Autodesk Fusion 360 part; units mm, degrees
(part 2 of 3)
extrude "Ламель 100 мм с пазами''''''''''''''''''" add sketch "Sketch1 (28)" along normal blind 16 separate body makes body 28 in component "Ламель ДСП 16 — 19"
ref_plane "WorkPlane2" through (0, 0, 0) normal (0, 1, 0) x (0, 0, 1) in component "Ламель ДСП 16 — 19"
sketch "Sketch2 (10)" plane through (0, 0, 0) normal (0, 1, 0) x (1, 0, 0) in component "Ламель ДСП 16 — 19"
  line L0 (-10, 8) -> (0.2209, 8)
  arc A0 (0.2209, 8) -> (0.2209, -8) centre (145, 0) ccw
  line L1 (0.2209, -8) -> (-10, -8)
  line L2 (-10, -8) -> (-10, 8)
extrude "Подгонка по радиусу наружной облицовки (4)" [suppressed] in component "ХДФ 3 — наружная обшивка — 2 шт"
extrude "Extrude11" [no effect] in component "Полистирол 2 — наружная обшивка — 2 шт"
extrude "Extrude2'''''''" cut sketch "Sketch2 (10)" along normal blind 998 bodies 28 in component "Ламель ДСП 16 — 19"
ref_plane "WorkPlane1" through (0, 0, -8) normal (0, 0, 1) x (1, 0, 0) in component "Ламель ДСП 16 — 20"
sketch "Sketch1 (29)" plane through (0, 0, -8) normal (0, 0, 1) x (1, 0, 0) in component "Ламель ДСП 16 — 20"
  line L0 (0, 0) -> (50, 0)
  line L1 (50, 0) -> (50, 16)
  line L2 (50, 16) -> (100, 16)
  line L3 (100, 16) -> (100, 245.5)
  line L4 (100, 245.5) -> (50, 245.5)
  line L5 (50, 245.5) -> (50, 261.5)
  line L6 (50, 261.5) -> (100, 261.5)
  line L7 (100, 261.5) -> (100, 491)
  line L8 (100, 491) -> (50, 491)
  line L9 (50, 491) -> (50, 507)
  line L10 (50, 507) -> (100, 507)
  line L11 (100, 507) -> (100, 736.5)
  line L12 (100, 736.5) -> (50, 736.5)
  line L13 (50, 736.5) -> (50, 752.5)
  line L14 (50, 752.5) -> (100, 752.5)
  line L15 (100, 752.5) -> (100, 982)
  line L16 (100, 982) -> (12.5, 982)
  line L17 (12.5, 982) -> (12.5, 998)
  line L18 (12.5, 998) -> (0, 998)
  line L19 (0, 998) -> (0, 0)
extrude "Ламель 100 мм с пазами'''''''''''''''''''" add sketch "Sketch1 (29)" along normal blind 16 separate body makes body 29 in component "Ламель ДСП 16 — 20"
ref_plane "WorkPlane2" through (0, 0, 0) normal (0, 1, 0) x (0, 0, 1) in component "Ламель ДСП 16 — 20"
sketch "Sketch2 (11)" plane through (0, 0, 0) normal (0, 1, 0) x (1, 0, 0) in component "Ламель ДСП 16 — 20"
  line L0 (-10, 8) -> (0.2209, 8)
  arc A0 (0.2209, 8) -> (0.2209, -8) centre (145, 0) ccw
  line L1 (0.2209, -8) -> (-10, -8)
  line L2 (-10, -8) -> (-10, 8)
extrude "Подгонка по радиусу наружной облицовки (5)" [suppressed] in component "ХДФ 3 — наружная обшивка — 2 шт"
extrude "Extrude12" [no effect] in component "Полистирол 2 — наружная обшивка — 2 шт"
extrude "Extrude2''''''''" cut sketch "Sketch2 (11)" along normal blind 998 bodies 29 in component "Ламель ДСП 16 — 20"
ref_plane "WorkPlane3" through (0, 0, -8) normal (0, 0, 1) x (1, 0, 0) in component "Ламель ДСП 16 — 18"
sketch "Sketch3" plane through (0, 0, -8) normal (0, 0, 1) x (1, 0, 0) in component "Ламель ДСП 16 — 18"
  line L0 (25, 850) -> (101, 850)
  line L1 (101, 850) -> (101, 982)
  line L2 (101, 982) -> (25, 982)
  line L3 (25, 982) -> (25, 850)
extrude "Освободить нишу под цветы" cut sketch "Sketch3" along normal blind 16 bodies 27 in component "Ламель ДСП 16 — 18"
ref_plane "WorkPlane3" through (0, 0, -8) normal (0, 0, 1) x (1, 0, 0) in component "Ламель ДСП 16 — 20"
sketch "Sketch3 (2)" plane through (0, 0, -8) normal (0, 0, 1) x (1, 0, 0) in component "Ламель ДСП 16 — 20"
  line L0 (25, 850) -> (101, 850)
  line L1 (101, 850) -> (101, 982)
  line L2 (101, 982) -> (25, 982)
  line L3 (25, 982) -> (25, 850)
extrude "Освободить нишу под цветы'" cut sketch "Sketch3 (2)" along normal blind 16 bodies 29 in component "Ламель ДСП 16 — 20"
ref_plane "WorkPlane2" through (0, 0, -8) normal (0, 0, 1) x (1, 0, 0) in component "Ламель ДСП 16 — 06"
sketch "Sketch2 (12)" plane through (0, 0, -8) normal (0, 0, 1) x (1, 0, 0) in component "Ламель ДСП 16 — 06"
  line L0 (25, 850) -> (101, 850)
  line L1 (101, 850) -> (101, 982)
  line L2 (101, 982) -> (25, 982)
  line L3 (25, 982) -> (25, 850)
extrude "Освободить нишу под цветы''" cut sketch "Sketch2 (12)" along normal blind 16 bodies 15 in component "Ламель ДСП 16 — 06"
ref_plane "WorkPlane2" through (0, 0, -8) normal (0, 0, 1) x (1, 0, 0) in component "Ламель ДСП 16 — 03"
sketch "Sketch2 (13)" plane through (0, 0, -8) normal (0, 0, 1) x (1, 0, 0) in component "Ламель ДСП 16 — 03"
  line L0 (25, 850) -> (101, 850)
  line L1 (101, 850) -> (101, 982)
  line L2 (101, 982) -> (25, 982)
  line L3 (25, 982) -> (25, 850)
extrude "Освободить нишу под цветы'''" cut sketch "Sketch2 (13)" along normal blind 16 bodies 12 in component "Ламель ДСП 16 — 03"
ref_plane "WorkPlane2" through (0, 0, -8) normal (0, 0, 1) x (1, 0, 0) in component "Ламель ДСП 16 — 04"
sketch "Sketch2 (14)" plane through (0, 0, -8) normal (0, 0, 1) x (1, 0, 0) in component "Ламель ДСП 16 — 04"
  line L0 (25, 850) -> (101, 850)
  line L1 (101, 850) -> (101, 982)
  line L2 (101, 982) -> (25, 982)
  line L3 (25, 982) -> (25, 850)
extrude "Освободить нишу под цветы''''" cut sketch "Sketch2 (14)" along normal blind 16 bodies 13 in component "Ламель ДСП 16 — 04"
ref_plane "WorkPlane2" through (0, 0, -8) normal (0, 0, 1) x (1, 0, 0) in component "Ламель ДСП 16 — 05"
sketch "Sketch2 (15)" plane through (0, 0, -8) normal (0, 0, 1) x (1, 0, 0) in component "Ламель ДСП 16 — 05"
  line L0 (25, 850) -> (101, 850)
  line L1 (101, 850) -> (101, 982)
  line L2 (101, 982) -> (25, 982)
  line L3 (25, 982) -> (25, 850)
extrude "Освободить нишу под цветы'''''" cut sketch "Sketch2 (15)" along normal blind 16 bodies 14 in component "Ламель ДСП 16 — 05"
ref_plane "WorkPlane2" through (0, 0, -8) normal (0, 0, 1) x (1, 0, 0) in component "Ламель ДСП 16 — 07"
sketch "Sketch2 (16)" plane through (0, 0, -8) normal (0, 0, 1) x (1, 0, 0) in component "Ламель ДСП 16 — 07"
  line L0 (25, 850) -> (101, 850)
  line L1 (101, 850) -> (101, 982)
  line L2 (101, 982) -> (25, 982)
  line L3 (25, 982) -> (25, 850)
extrude "Освободить нишу под цветы''''''" cut sketch "Sketch2 (16)" along normal blind 16 bodies 16 in component "Ламель ДСП 16 — 07"
ref_plane "WorkPlane2" through (0, 0, -8) normal (0, 0, 1) x (1, 0, 0) in component "Ламель ДСП 16 — 09"
sketch "Sketch2 (17)" plane through (0, 0, -8) normal (0, 0, 1) x (1, 0, 0) in component "Ламель ДСП 16 — 09"
  line L0 (25, 850) -> (101, 850)
  line L1 (101, 850) -> (101, 982)
  line L2 (101, 982) -> (25, 982)
  line L3 (25, 982) -> (25, 850)
extrude "Освободить нишу под цветы'''''''" cut sketch "Sketch2 (17)" along normal blind 16 bodies 18 in component "Ламель ДСП 16 — 09"
ref_plane "WorkPlane2" through (0, 0, -8) normal (0, 0, 1) x (1, 0, 0) in component "Ламель ДСП 16 — 12"
sketch "Sketch2 (18)" plane through (0, 0, -8) normal (0, 0, 1) x (1, 0, 0) in component "Ламель ДСП 16 — 12"
  line L0 (25, 850) -> (101, 850)
  line L1 (101, 850) -> (101, 982)
  line L2 (101, 982) -> (25, 982)
  line L3 (25, 982) -> (25, 850)
extrude "Освободить нишу под цветы''''''''" cut sketch "Sketch2 (18)" along normal blind 16 bodies 21 in component "Ламель ДСП 16 — 12"
ref_plane "WorkPlane2" through (0, 0, -8) normal (0, 0, 1) x (1, 0, 0) in component "Ламель ДСП 16 — 08"
sketch "Sketch2 (19)" plane through (0, 0, -8) normal (0, 0, 1) x (1, 0, 0) in component "Ламель ДСП 16 — 08"
  line L0 (25, 850) -> (101, 850)
  line L1 (101, 850) -> (101, 982)
  line L2 (101, 982) -> (25, 982)
  line L3 (25, 982) -> (25, 850)
extrude "Освободить нишу под цветы'''''''''" cut sketch "Sketch2 (19)" along normal blind 16 bodies 17 in component "Ламель ДСП 16 — 08"
ref_plane "WorkPlane2" through (0, 0, -8) normal (0, 0, 1) x (1, 0, 0) in component "Ламель ДСП 16 — 10"
sketch "Sketch2 (20)" plane through (0, 0, -8) normal (0, 0, 1) x (1, 0, 0) in component "Ламель ДСП 16 — 10"
  line L0 (25, 850) -> (101, 850)
  line L1 (101, 850) -> (101, 982)
  line L2 (101, 982) -> (25, 982)
  line L3 (25, 982) -> (25, 850)
extrude "Освободить нишу под цветы''''''''''" cut sketch "Sketch2 (20)" along normal blind 16 bodies 19 in component "Ламель ДСП 16 — 10"
ref_plane "WorkPlane2" through (0, 0, -8) normal (0, 0, 1) x (1, 0, 0) in component "Ламель ДСП 16 — 11"
sketch "Sketch2 (21)" plane through (0, 0, -8) normal (0, 0, 1) x (1, 0, 0) in component "Ламель ДСП 16 — 11"
  line L0 (25, 850) -> (101, 850)
  line L1 (101, 850) -> (101, 982)
  line L2 (101, 982) -> (25, 982)
  line L3 (25, 982) -> (25, 850)
extrude "Освободить нишу под цветы'''''''''''" cut sketch "Sketch2 (21)" along normal blind 16 bodies 20 in component "Ламель ДСП 16 — 11"
ref_plane "WorkPlane3" through (0, 0, -8) normal (0, 0, 1) x (1, 0, 0) in component "Ламель ДСП 16 — 16"
sketch "Sketch3 (3)" plane through (0, 0, -8) normal (0, 0, 1) x (1, 0, 0) in component "Ламель ДСП 16 — 16"
  line L0 (25, 850) -> (101, 850)
  line L1 (101, 850) -> (101, 982)
  line L2 (101, 982) -> (25, 982)
  line L3 (25, 982) -> (25, 850)
extrude "Освободить нишу под цветы''''''''''''" cut sketch "Sketch3 (3)" along normal blind 16 bodies 25 in component "Ламель ДСП 16 — 16"
ref_plane "WorkPlane3" through (0, 0, -8) normal (0, 0, 1) x (1, 0, 0) in component "Ламель ДСП 16 — 19"
sketch "Sketch3 (4)" plane through (0, 0, -8) normal (0, 0, 1) x (1, 0, 0) in component "Ламель ДСП 16 — 19"
  line L0 (25, 850) -> (101, 850)
  line L1 (101, 850) -> (101, 982)
  line L2 (101, 982) -> (25, 982)
  line L3 (25, 982) -> (25, 850)
extrude "Освободить нишу под цветы'''''''''''''" cut sketch "Sketch3 (4)" along normal blind 16 bodies 28 in component "Ламель ДСП 16 — 19"
ref_plane "WorkPlane2" through (0, 0, -8) normal (0, 0, 1) x (1, 0, 0) in component "Ламель ДСП 16 — 14"
sketch "Sketch2 (22)" plane through (0, 0, -8) normal (0, 0, 1) x (1, 0, 0) in component "Ламель ДСП 16 — 14"
  line L0 (25, 850) -> (101, 850)
  line L1 (101, 850) -> (101, 982)
  line L2 (101, 982) -> (25, 982)
  line L3 (25, 982) -> (25, 850)
extrude "Освободить нишу под цветы''''''''''''''" cut sketch "Sketch2 (22)" along normal blind 16 bodies 23 in component "Ламель ДСП 16 — 14"
ref_plane "WorkPlane2" through (0, 0, -8) normal (0, 0, 1) x (1, 0, 0) in component "Ламель ДСП 16 — 13"
sketch "Sketch2 (23)" plane through (0, 0, -8) normal (0, 0, 1) x (1, 0, 0) in component "Ламель ДСП 16 — 13"
  line L0 (25, 850) -> (101, 850)
  line L1 (101, 850) -> (101, 982)
  line L2 (101, 982) -> (25, 982)
  line L3 (25, 982) -> (25, 850)
extrude "Освободить нишу под цветы'''''''''''''''" cut sketch "Sketch2 (23)" along normal blind 16 bodies 22 in component "Ламель ДСП 16 — 13"
ref_plane "WorkPlane3" through (0, 0, -8) normal (0, 0, 1) x (1, 0, 0) in component "Ламель ДСП 16 — 15"
sketch "Sketch3 (5)" plane through (0, 0, -8) normal (0, 0, 1) x (1, 0, 0) in component "Ламель ДСП 16 — 15"
  line L0 (25, 850) -> (101, 850)
  line L1 (101, 850) -> (101, 982)
  line L2 (101, 982) -> (25, 982)
  line L3 (25, 982) -> (25, 850)
extrude "Освободить нишу под цветы''''''''''''''''" cut sketch "Sketch3 (5)" along normal blind 16 bodies 24 in component "Ламель ДСП 16 — 15"
ref_plane "WorkPlane2" through (0, 0, -8) normal (0, 0, 1) x (1, 0, 0) in component "Ламель ДСП 16 — 02"
sketch "Sketch2 (24)" plane through (0, 0, -8) normal (0, 0, 1) x (1, 0, 0) in component "Ламель ДСП 16 — 02"
  line L0 (25, 850) -> (101, 850)
  line L1 (101, 850) -> (101, 982)
  line L2 (101, 982) -> (25, 982)
  line L3 (25, 982) -> (25, 850)
extrude "Освободить нишу под цветы'''''''''''''''''" cut sketch "Sketch2 (24)" along normal blind 16 bodies 11 in component "Ламель ДСП 16 — 02"
ref_plane "WorkPlane2" through (0, 0, -8) normal (0, 0, 1) x (1, 0, 0) in component "Ламель ДСП 16 — 01"
sketch "Sketch2 (25)" plane through (0, 0, -8) normal (0, 0, 1) x (1, 0, 0) in component "Ламель ДСП 16 — 01"
  line L0 (25, 850) -> (101, 850)
  line L1 (101, 850) -> (101, 982)
  line L2 (101, 982) -> (25, 982)
  line L3 (25, 982) -> (25, 850)
extrude "Освободить нишу под цветы''''''''''''''''''" cut sketch "Sketch2 (25)" along normal blind 16 bodies 10 in component "Ламель ДСП 16 — 01"
ref_plane "WorkPlane3" through (0, 0, -8) normal (0, 0, 1) x (1, 0, 0) in component "Ламель ДСП 16 — 17"
sketch "Sketch3 (6)" plane through (0, 0, -8) normal (0, 0, 1) x (1, 0, 0) in component "Ламель ДСП 16 — 17"
  line L0 (25, 850) -> (101, 850)
  line L1 (101, 850) -> (101, 982)
  line L2 (101, 982) -> (25, 982)
  line L3 (25, 982) -> (25, 850)
extrude "Освободить нишу под цветы'''''''''''''''''''" cut sketch "Sketch3 (6)" along normal blind 16 bodies 26 in component "Ламель ДСП 16 — 17"
copy_body "CutPasteBodies1" bodies 2 3 4 5 removing the originals makes body 30 makes body 31 makes body 32 makes body 33 in component "ДСП 16 — горизонтали с пазами 990х290х16 мм — 4 шт"
copy_body "CutPasteBodies1'" bodies 10 11 12 13 14 15 16 17 18 19 20 21 22 23 body 10 seen with x (0, 0, 1) y (0, 1, 0) z (-1, 0, 0) at (200, 0, 5) body 11 seen with x (0, 0, 1) y (0, 1, 0) z (-1, 0, 0) at (300, 0, 5) body 12 seen with x (0, 0, 1) y (0, 1, 0) z (-1, 0, 0) at (400, 0, 5) body 13 seen with x (0, 0, 1) y (0, 1, 0) z (-1, 0, 0) at (500, 0, 5) body 14 seen with x (0, 0, 1) y (0, 1, 0) z (-1, 0, 0) at (600, 0, 5) body 15 seen with x (0, 0, 1) y (0, 1, 0) z (-1, 0, 0) at (700, 0, 5) body 16 seen with x (0, 0, 1) y (0, 1, 0) z (-1, 0, 0) at (800, 0, 5) body 17 seen with x (0, 0, -1) y (0, 1, 0) z (1, 0, 0) at (200, 0, 295) body 18 seen with x (0, 0, -1) y (0, 1, 0) z (1, 0, 0) at (300, 0, 295) body 19 seen with x (0, 0, -1) y (0, 1, 0) z (1, 0, 0) at (400, 0, 295) body 20 seen with x (0, 0, -1) y (0, 1, 0) z (1, 0, 0) at (500, 0, 295) body 21 seen with x (0, 0, -1) y (0, 1, 0) z (1, 0, 0) at (600, 0, 295) body 22 seen with x (0, 0, -1) y (0, 1, 0) z (1, 0, 0) at (700, 0, 295) body 23 seen with x (0, 0, -1) y (0, 1, 0) z (1, 0, 0) at (800, 0, 295) removing the originals makes body 34 makes body 35 makes body 36 makes body 37 makes body 38 makes body 39 makes body 40 makes body 41 makes body 42 makes body 43 makes body 44 makes body 45 makes body 46 makes body 47 in component "ДСП 16 — ламель прямая 982х100х16 мм — 8 шт"
copy_body "CutPasteBodies1''" bodies 24 25 26 27 28 29 body 24 seen with x (-0.5, 0, 0.866025) y (0, 1, 0) z (-0.866025, 0, -0.5) at (922.5, 0, 24.4263) body 25 seen with x (-1, 0, 0) y (0, 1, 0) z (0, 0, -1) at (995, 0, 150) body 26 seen with x (-0.5, 0, -0.866025) y (0, 1, 0) z (0.866025, 0, -0.5) at (922.5, 0, 275.5737) body 27 seen with x (0.5, 0, -0.866025) y (0, 1, 0) z (0.866025, 0, 0.5) at (77.5, 0, 275.5737) body 28 seen with x (1, 0, 0) y (0, 1, 0) z (0, 0, 1) at (5, 0, 150) body 29 seen with x (0.5, 0, 0.866025) y (0, 1, 0) z (-0.866025, 0, 0.5) at (77.5, 0, 24.4263) removing the originals makes body 48 makes body 49 makes body 50 makes body 51 makes body 52 makes body 53 in component "ДСП 16 — ламель радиусная 982х100х16 мм — 6 шт"
ref_plane "WorkPlane1" through (0, 850, 0) normal (0, 1, 0) x (0, 0, 1) in component "ДСП 16 — дно ниши 940х240х16 мм — 1 шт"
sketch "Sketch1 (30)" plane through (0, 850, 0) normal (0, 1, 0) x (1, 0, 0) in component "ДСП 16 — дно ниши 940х240х16 мм — 1 шт"
  line L0 (150, -30) -> (850, -30)
  arc A0 (850, -270) -> (850, -30) centre (850, -150) ccw
  line L1 (850, -270) -> (150, -270)
  arc A1 (150, -30) -> (150, -270) centre (150, -150) ccw
extrude "Дно из ДСП 16 мм" add sketch "Sketch1 (30)" along normal blind 16 separate body makes body 54 in component "ДСП 16 — дно ниши 940х240х16 мм — 1 шт"
delete_body "RemoveBody1" bodies 35 in component "ДСП 16 — ламель прямая 982х100х16 мм — 8 шт"
delete_body "RemoveBody2" bodies 37 in component "ДСП 16 — ламель прямая 982х100х16 мм — 8 шт"
delete_body "RemoveBody3" bodies 39 in component "ДСП 16 — ламель прямая 982х100х16 мм — 8 шт"
delete_body "RemoveBody4" bodies 42 in component "ДСП 16 — ламель прямая 982х100х16 мм — 8 шт"
delete_body "RemoveBody5" bodies 44 in component "ДСП 16 — ламель прямая 982х100х16 мм — 8 шт"
delete_body "RemoveBody6" bodies 46 in component "ДСП 16 — ламель прямая 982х100х16 мм — 8 шт"
ref_plane "WorkPlane1" through (0, 982, 0) normal (0, 1, 0) x (0, 0, 1) in component "ДСП 16 — ламель прямая 982х100х16 мм — 8 шт"
sketch "Sketch1 (31)" plane through (0, 982, 0) normal (0, 1, 0) x (1, 0, 0) in component "ДСП 16 — ламель прямая 982х100х16 мм — 8 шт"
  line L0 (-100, 100) -> (1100, 100)
  line L1 (1100, 100) -> (1100, -400)
  line L2 (1100, -400) -> (-100, -400)
  line L3 (-100, -400) -> (-100, 100)
extrude "Ламели встык под верхнее кольцо" cut sketch "Sketch1 (31)" along normal blind 16 bodies 34 36 38 40 41 43 45 47 in component "ДСП 16 — ламель прямая 982х100х16 мм — 8 шт"
ref_plane "WorkPlane1" through (0, 982, 0) normal (0, 1, 0) x (0, 0, 1) in component "ДСП 16 — ламель радиусная 982х100х16 мм — 6 шт"
sketch "Sketch1 (32)" plane through (0, 982, 0) normal (0, 1, 0) x (1, 0, 0) in component "ДСП 16 — ламель радиусная 982х100х16 мм — 6 шт"
  line L0 (-100, 100) -> (1100, 100)
  line L1 (1100, 100) -> (1100, -400)
  line L2 (1100, -400) -> (-100, -400)
  line L3 (-100, -400) -> (-100, 100)
extrude "Ламели встык под верхнее кольцо'" cut sketch "Sketch1 (32)" along normal blind 16 bodies 48 49 50 51 52 53 in component "ДСП 16 — ламель радиусная 982х100х16 мм — 6 шт"
ref_plane "WorkPlane1" through (-100, 0, 0) normal (1, 0, 0) x (0, 1, 0) in component "Вспомогательный контур стыка ХДФ"
sketch "Sketch1 (33)" plane through (-100, 0, 0) normal (1, 0, 0) x (0, 0, -1) in component "Вспомогательный контур стыка ХДФ"
  line L0 (100, -100) -> (100, 1100)
  line L1 (100, 1100) -> (-146, 1100)
  line L2 (-146, 1100) -> (-146, 998)
  line L3 (-146, 998) -> (-146, 948.1)
  line L4 (-146, 948.1) -> (-154, 948.1)
  line L5 (-154, 948.1) -> (-154, 898.2)
  line L6 (-154, 898.2) -> (-146, 898.2)
  line L7 (-146, 898.2) -> (-146, 848.3)
  line L8 (-146, 848.3) -> (-154, 848.3)
  line L9 (-154, 848.3) -> (-154, 798.4)
  line L10 (-154, 798.4) -> (-146, 798.4)
  line L11 (-146, 798.4) -> (-146, 748.5)
  line L12 (-146, 748.5) -> (-154, 748.5)
  line L13 (-154, 748.5) -> (-154, 698.6)
  line L14 (-154, 698.6) -> (-146, 698.6)
  line L15 (-146, 698.6) -> (-146, 648.7)
  line L16 (-146, 648.7) -> (-154, 648.7)
  line L17 (-154, 648.7) -> (-154, 598.8)
  line L18 (-154, 598.8) -> (-146, 598.8)
  line L19 (-146, 598.8) -> (-146, 548.9)
  line L20 (-146, 548.9) -> (-154, 548.9)
  line L21 (-154, 548.9) -> (-154, 499)
  line L22 (-154, 499) -> (-146, 499)
  line L23 (-146, 499) -> (-146, 449.1)
  line L24 (-146, 449.1) -> (-154, 449.1)
  line L25 (-154, 449.1) -> (-154, 399.2)
  line L26 (-154, 399.2) -> (-146, 399.2)
  line L27 (-146, 399.2) -> (-146, 349.3)
  line L28 (-146, 349.3) -> (-154, 349.3)
  line L29 (-154, 349.3) -> (-154, 299.4)
  line L30 (-154, 299.4) -> (-146, 299.4)
  line L31 (-146, 299.4) -> (-146, 249.5)
  line L32 (-146, 249.5) -> (-154, 249.5)
  line L33 (-154, 249.5) -> (-154, 199.6)
  line L34 (-154, 199.6) -> (-146, 199.6)
  line L35 (-146, 199.6) -> (-146, 149.7)
  line L36 (-146, 149.7) -> (-154, 149.7)
  line L37 (-154, 149.7) -> (-154, 99.8)
  line L38 (-154, 99.8) -> (-146, 99.8)
  line L39 (-146, 99.8) -> (-146, 49.9)
  line L40 (-146, 49.9) -> (-154, 49.9)
  line L41 (-154, 49.9) -> (-154, 0)
  line L42 (-154, 0) -> (-154, -100)
  line L43 (-154, -100) -> (100, -100)
extrude "Инструмент разреза ХДФ" add sketch "Sketch1 (33)" along normal blind 1200 separate body makes body 55 in component "Вспомогательный контур стыка ХДФ"
split "Стыки ХДФ на ламелях — шип-паз" [suppressed] in component "ХДФ 3 — наружная обшивка — 2 шт"
ref_plane "WorkPlane2" through (500, 0, 0) normal (1, 0, 0) x (0, 1, 0) in component "Полистирол 2 — наружная обшивка — 2 шт"
split "Стыки полистирола по прямым сторонам" by plane through (500, 0, 0) normal (1, 0, 0) bodies 8 makes body 56 at (887.0136, 665.3333, 4.6384) in component "Полистирол 2 — наружная обшивка — 2 шт"
ref_plane "WorkPlane1" through (0, 0, -100) normal (0, 0, 1) x (1, 0, 0) in component "Вспомогательный контур прямого стыка ХДФ"
sketch "Sketch1 (34)" plane through (0, 0, -100) normal (0, 0, 1) x (1, 0, 0) in component "Вспомогательный контур прямого стыка ХДФ"
  line L0 (-100, -100) -> (-100, 1100)
  line L1 (-100, 1100) -> (396, 1100)
  line L2 (396, 1100) -> (396, 998)
  line L3 (396, 998) -> (396, 948.1)
  line L4 (396, 948.1) -> (404, 948.1)
  line L5 (404, 948.1) -> (404, 898.2)
  line L6 (404, 898.2) -> (396, 898.2)
  line L7 (396, 898.2) -> (396, 848.3)
  line L8 (396, 848.3) -> (404, 848.3)
  line L9 (404, 848.3) -> (404, 798.4)
  line L10 (404, 798.4) -> (396, 798.4)
  line L11 (396, 798.4) -> (396, 748.5)
  line L12 (396, 748.5) -> (404, 748.5)
  line L13 (404, 748.5) -> (404, 698.6)
  line L14 (404, 698.6) -> (396, 698.6)
  line L15 (396, 698.6) -> (396, 648.7)
  line L16 (396, 648.7) -> (404, 648.7)
  line L17 (404, 648.7) -> (404, 598.8)
  line L18 (404, 598.8) -> (396, 598.8)
  line L19 (396, 598.8) -> (396, 548.9)
  line L20 (396, 548.9) -> (404, 548.9)
  line L21 (404, 548.9) -> (404, 499)
  line L22 (404, 499) -> (396, 499)
  line L23 (396, 499) -> (396, 449.1)
  line L24 (396, 449.1) -> (404, 449.1)
  line L25 (404, 449.1) -> (404, 399.2)
  line L26 (404, 399.2) -> (396, 399.2)
  line L27 (396, 399.2) -> (396, 349.3)
  line L28 (396, 349.3) -> (404, 349.3)
  line L29 (404, 349.3) -> (404, 299.4)
  line L30 (404, 299.4) -> (396, 299.4)
  line L31 (396, 299.4) -> (396, 249.5)
  line L32 (396, 249.5) -> (404, 249.5)
  line L33 (404, 249.5) -> (404, 199.6)
  line L34 (404, 199.6) -> (396, 199.6)
  line L35 (396, 199.6) -> (396, 149.7)
  line L36 (396, 149.7) -> (404, 149.7)
  line L37 (404, 149.7) -> (404, 99.8)
  line L38 (404, 99.8) -> (396, 99.8)
  line L39 (396, 99.8) -> (396, 49.9)
  line L40 (396, 49.9) -> (404, 49.9)
  line L41 (404, 49.9) -> (404, 0)
  line L42 (404, 0) -> (404, -100)
  line L43 (404, -100) -> (-100, -100)
extrude "Extrude1'" add sketch "Sketch1 (34)" along normal blind 500 separate body makes body 57 in component "Вспомогательный контур прямого стыка ХДФ"
split "Стыки ХДФ по прямым ламелям — шип-паз" by bodies 57 bodies 7 makes body 58 at (939.3631, 665.3333, 267.9756) in component "ХДФ 3 — наружная обшивка — 2 шт"
ref_plane "WorkPlane1" through (0, 0, 0) normal (0, 1, 0) x (0, 0, 1) in component "ДСП 16 — горизонтали с пазами 990х290х16 мм — 4 шт"
sketch "Sketch1 (35)" plane through (0, 0, 0) normal (0, 1, 0) x (1, 0, 0) in component "ДСП 16 — горизонтали с пазами 990х290х16 мм — 4 шт"
  line L0 (208.1, 0) -> (208.1, -55)
  line L1 (208.1, -55) -> (191.9, -55)
  line L2 (191.9, -55) -> (191.9, 0)
  line L3 (191.9, 0) -> (208.1, 0)
  line L4 (408.1, 0) -> (408.1, -55)
  line L5 (408.1, -55) -> (391.9, -55)
  line L6 (391.9, -55) -> (391.9, 0)
  line L7 (391.9, 0) -> (408.1, 0)
  line L8 (608.1, 0) -> (608.1, -55)
  line L9 (608.1, -55) -> (591.9, -55)
  line L10 (591.9, -55) -> (591.9, 0)
  line L11 (591.9, 0) -> (608.1, 0)
  line L12 (808.1, 0) -> (808.1, -55)
  line L13 (808.1, -55) -> (791.9, -55)
  line L14 (791.9, -55) -> (791.9, 0)
  line L15 (791.9, 0) -> (808.1, 0)
  line L16 (191.9, -300) -> (191.9, -245)
  line L17 (191.9, -245) -> (208.1, -245)
  line L18 (208.1, -245) -> (208.1, -300)
  line L19 (208.1, -300) -> (191.9, -300)
  line L20 (391.9, -300) -> (391.9, -245)
  line L21 (391.9, -245) -> (408.1, -245)
  line L22 (408.1, -245) -> (408.1, -300)
  line L23 (408.1, -300) -> (391.9, -300)
  line L24 (591.9, -300) -> (591.9, -245)
  line L25 (591.9, -245) -> (608.1, -245)
  line L26 (608.1, -245) -> (608.1, -300)
  line L27 (608.1, -300) -> (591.9, -300)
  line L28 (791.9, -300) -> (791.9, -245)
  line L29 (791.9, -245) -> (808.1, -245)
  line L30 (808.1, -245) -> (808.1, -300)
  line L31 (808.1, -300) -> (791.9, -300)
  line L32 (932.0148, -24.1462) -> (904.5148, -71.7776)
  line L33 (904.5148, -71.7776) -> (890.4852, -63.6776)
  line L34 (890.4852, -63.6776) -> (917.9852, -16.0462)
  line L35 (917.9852, -16.0462) -> (932.0148, -24.1462)
  line L36 (1000, -158.1) -> (945, -158.1)
  line L37 (945, -158.1) -> (945, -141.9)
  line L38 (945, -141.9) -> (1000, -141.9)
  line L39 (1000, -141.9) -> (1000, -158.1)
  line L40 (917.9852, -283.9538) -> (890.4852, -236.3224)
  line L41 (890.4852, -236.3224) -> (904.5148, -228.2224)
  line L42 (904.5148, -228.2224) -> (932.0148, -275.8538)
  line L43 (932.0148, -275.8538) -> (917.9852, -283.9538)
  line L44 (67.9852, -275.8538) -> (95.4852, -228.2224)
  line L45 (95.4852, -228.2224) -> (109.5148, -236.3224)
  line L46 (109.5148, -236.3224) -> (82.0148, -283.9538)
  line L47 (82.0148, -283.9538) -> (67.9852, -275.8538)
  line L48 (0, -141.9) -> (55, -141.9)
  line L49 (55, -141.9) -> (55, -158.1)
  line L50 (55, -158.1) -> (0, -158.1)
  line L51 (0, -158.1) -> (0, -141.9)
  line L52 (82.0148, -16.0462) -> (109.5148, -63.6776)
  line L53 (109.5148, -63.6776) -> (95.4852, -71.7776)
  line L54 (95.4852, -71.7776) -> (67.9852, -24.1462)
  line L55 (67.9852, -24.1462) -> (82.0148, -16.0462)
extrude "Зазор пазов +0,2 мм" cut sketch "Sketch1 (35)" along normal blind 752.5 bodies 30 31 32 33 in component "ДСП 16 — горизонтали с пазами 990х290х16 мм — 4 шт"
sketch "Sketch2 (26)" plane through (0, 0, 0) normal (0, 1, 0) x (1, 0, 0) in component "ДСП 16 — горизонтали с пазами 990х290х16 мм — 4 шт"
  circle A0 centre (206.6151, -53.5151) radius 2.1
  circle A1 centre (193.3849, -53.5151) radius 2.1
  circle A2 centre (406.6151, -53.5151) radius 2.1
  circle A3 centre (393.3849, -53.5151) radius 2.1
  circle A4 centre (606.6151, -53.5151) radius 2.1
  circle A5 centre (593.3849, -53.5151) radius 2.1
  circle A6 centre (806.6151, -53.5151) radius 2.1
  circle A7 centre (793.3849, -53.5151) radius 2.1
  circle A8 centre (193.3849, -246.4849) radius 2.1
  circle A9 centre (206.6151, -246.4849) radius 2.1
  circle A10 centre (393.3849, -246.4849) radius 2.1
  circle A11 centre (406.6151, -246.4849) radius 2.1
  circle A12 centre (593.3849, -246.4849) radius 2.1
  circle A13 centre (606.6151, -246.4849) radius 2.1
  circle A14 centre (793.3849, -246.4849) radius 2.1
  circle A15 centre (806.6151, -246.4849) radius 2.1
  circle A16 centre (903.9713, -69.7491) radius 2.1
  circle A17 centre (892.5136, -63.1341) radius 2.1
  circle A18 centre (946.4849, -156.6151) radius 2.1
  circle A19 centre (946.4849, -143.3849) radius 2.1
  circle A20 centre (892.5136, -236.8659) radius 2.1
  circle A21 centre (903.9713, -230.2509) radius 2.1
  circle A22 centre (96.0287, -230.2509) radius 2.1
  circle A23 centre (107.4864, -236.8659) radius 2.1
  circle A24 centre (53.5151, -143.3849) radius 2.1
  circle A25 centre (53.5151, -156.6151) radius 2.1
  circle A26 centre (107.4864, -63.1341) radius 2.1
  circle A27 centre (96.0287, -69.7491) radius 2.1
extrude "Компактные догбоны Ø4,2 мм" cut sketch "Sketch2 (26)" along normal blind 752.5 bodies 30 31 32 33 in component "ДСП 16 — горизонтали с пазами 990х290х16 мм — 4 шт"
sketch "Sketch2 (27)" plane through (192, 0, 0) normal (-1, 0, 0) x (0, 0, 1) in component "ДСП 16 — ламель прямая 982х100х16 мм — 8 шт"
  line L0 (30, 982) -> (5, 982) construction
  line L1 (5, 982) -> (5, 0) construction
  line L2 (5, 0) -> (55, 0) construction
  line L3 (55, 0) -> (55, 16) construction
  line L4 (55, 16) -> (105, 16) construction
  line L5 (105, 16) -> (105, 245.5) construction
  line L6 (105, 245.5) -> (55, 245.5) construction
  line L7 (55, 245.5) -> (55, 261.5) construction
  line L8 (55, 261.5) -> (105, 261.5) construction
  line L9 (105, 261.5) -> (105, 491) construction
  line L10 (105, 491) -> (55, 491) construction
  line L11 (55, 491) -> (55, 507) construction
  line L12 (55, 507) -> (105, 507) construction
  line L13 (105, 507) -> (105, 736.5) construction
  line L14 (105, 736.5) -> (55, 736.5) construction
  line L15 (55, 736.5) -> (55, 752.5) construction
  line L16 (55, 752.5) -> (105, 752.5) construction
  line L17 (105, 752.5) -> (105, 850) construction
  line L18 (105, 850) -> (30, 850) construction
  line L19 (30, 850) -> (30, 982) construction
  line L20 (55, -0.1) -> (107, -0.1)
  line L21 (107, -0.1) -> (107, 16.1)
  line L22 (107, 16.1) -> (55, 16.1)
  line L23 (55, 16.1) -> (55, -0.1)
  line L24 (55, 245.4) -> (107, 245.4)
  line L25 (107, 245.4) -> (107, 261.6)
  line L26 (107, 261.6) -> (55, 261.6)
  line L27 (55, 261.6) -> (55, 245.4)
  line L28 (55, 490.9) -> (107, 490.9)
  line L29 (107, 490.9) -> (107, 507.1)
  line L30 (107, 507.1) -> (55, 507.1)
  line L31 (55, 507.1) -> (55, 490.9)
  line L32 (55, 736.4) -> (107, 736.4)
  line L33 (107, 736.4) -> (107, 752.6)
  line L34 (107, 752.6) -> (55, 752.6)
  line L35 (55, 752.6) -> (55, 736.4)
extrude "Зазор паза +0,2 мм Тело 01" cut sketch "Sketch2 (27)" along normal mid plane 80 bodies 34 in component "ДСП 16 — ламель прямая 982х100х16 мм — 8 шт"
sketch "Sketch3 (7)" plane through (208, 0, 0) normal (1, 0, 0) x (0, 0, -1) in component "ДСП 16 — ламель прямая 982х100х16 мм — 8 шт"
  line L0 (-105, 507.1) -> (-55, 507.1) construction
  line L1 (-55, 507.1) -> (-55, 490.9) construction
  line L2 (-55, 490.9) -> (-105, 490.9) construction
  line L3 (-105, 490.9) -> (-105, 261.6) construction
  line L4 (-105, 261.6) -> (-55, 261.6) construction
  line L5 (-55, 261.6) -> (-55, 245.4) construction
  line L6 (-55, 245.4) -> (-105, 245.4) construction
  line L7 (-105, 245.4) -> (-105, 16.1) construction
  line L8 (-105, 16.1) -> (-55, 16.1) construction
  line L9 (-55, 16.1) -> (-55, 0) construction
  line L10 (-55, 0) -> (-5, 0) construction
  line L11 (-5, 0) -> (-5, 982) construction
  line L12 (-5, 982) -> (-30, 982) construction
  line L13 (-30, 982) -> (-30, 850) construction
  line L14 (-30, 850) -> (-105, 850) construction
  line L15 (-105, 850) -> (-105, 752.6) construction
  line L16 (-105, 752.6) -> (-55, 752.6) construction
  line L17 (-55, 752.6) -> (-55, 736.4) construction
  line L18 (-55, 736.4) -> (-105, 736.4) construction
  line L19 (-105, 736.4) -> (-105, 507.1) construction
  circle A0 centre (-56.4849, 14.6151) radius 2.1
  circle A1 centre (-56.4849, 246.8849) radius 2.1
  circle A2 centre (-56.4849, 260.1151) radius 2.1
  circle A3 centre (-56.4849, 492.3849) radius 2.1
  circle A4 centre (-56.4849, 505.6151) radius 2.1
  circle A5 centre (-56.4849, 737.8849) radius 2.1
  circle A6 centre (-56.4849, 751.1151) radius 2.1
extrude "Догбон Ø4,2 мм Тело 01" cut sketch "Sketch3 (7)" along normal mid plane 80 bodies 34 in component "ДСП 16 — ламель прямая 982х100х16 мм — 8 шт"
sketch "Sketch4" plane through (392, 0, 0) normal (-1, 0, 0) x (0, 0, 1) in component "ДСП 16 — ламель прямая 982х100х16 мм — 8 шт"
  line L0 (30, 982) -> (5, 982) construction
  line L1 (5, 982) -> (5, 0) construction
  line L2 (5, 0) -> (55, 0) construction
  line L3 (55, 0) -> (55, 16) construction
  line L4 (55, 16) -> (105, 16) construction
  line L5 (105, 16) -> (105, 245.5) construction
  line L6 (105, 245.5) -> (55, 245.5) construction
  line L7 (55, 245.5) -> (55, 261.5) construction
  line L8 (55, 261.5) -> (105, 261.5) construction
  line L9 (105, 261.5) -> (105, 491) construction
  line L10 (105, 491) -> (55, 491) construction
  line L11 (55, 491) -> (55, 507) construction
  line L12 (55, 507) -> (105, 507) construction
  line L13 (105, 507) -> (105, 736.5) construction
  line L14 (105, 736.5) -> (55, 736.5) construction
  line L15 (55, 736.5) -> (55, 752.5) construction
  line L16 (55, 752.5) -> (105, 752.5) construction
  line L17 (105, 752.5) -> (105, 850) construction
  line L18 (105, 850) -> (30, 850) construction
  line L19 (30, 850) -> (30, 982) construction
  line L20 (55, -0.1) -> (107, -0.1)
  line L21 (107, -0.1) -> (107, 16.1)
  line L22 (107, 16.1) -> (55, 16.1)
  line L23 (55, 16.1) -> (55, -0.1)
  line L24 (55, 245.4) -> (107, 245.4)
  line L25 (107, 245.4) -> (107, 261.6)
  line L26 (107, 261.6) -> (55, 261.6)
  line L27 (55, 261.6) -> (55, 245.4)
  line L28 (55, 490.9) -> (107, 490.9)
  line L29 (107, 490.9) -> (107, 507.1)
  line L30 (107, 507.1) -> (55, 507.1)
  line L31 (55, 507.1) -> (55, 490.9)
  line L32 (55, 736.4) -> (107, 736.4)
  line L33 (107, 736.4) -> (107, 752.6)
  line L34 (107, 752.6) -> (55, 752.6)
  line L35 (55, 752.6) -> (55, 736.4)
extrude "Зазор паза +0,2 мм Тело 03" cut sketch "Sketch4" along normal mid plane 80 bodies 36 in component "ДСП 16 — ламель прямая 982х100х16 мм — 8 шт"
sketch "Sketch5" plane through (408, 0, 0) normal (1, 0, 0) x (0, 0, -1) in component "ДСП 16 — ламель прямая 982х100х16 мм — 8 шт"
  line L0 (-105, 507.1) -> (-55, 507.1) construction
  line L1 (-55, 507.1) -> (-55, 490.9) construction
  line L2 (-55, 490.9) -> (-105, 490.9) construction
  line L3 (-105, 490.9) -> (-105, 261.6) construction
  line L4 (-105, 261.6) -> (-55, 261.6) construction
  line L5 (-55, 261.6) -> (-55, 245.4) construction
  line L6 (-55, 245.4) -> (-105, 245.4) construction
  line L7 (-105, 245.4) -> (-105, 16.1) construction
  line L8 (-105, 16.1) -> (-55, 16.1) construction
  line L9 (-55, 16.1) -> (-55, 0) construction
  line L10 (-55, 0) -> (-5, 0) construction
  line L11 (-5, 0) -> (-5, 982) construction
  line L12 (-5, 982) -> (-30, 982) construction
  line L13 (-30, 982) -> (-30, 850) construction
  line L14 (-30, 850) -> (-105, 850) construction
  line L15 (-105, 850) -> (-105, 752.6) construction
  line L16 (-105, 752.6) -> (-55, 752.6) construction
  line L17 (-55, 752.6) -> (-55, 736.4) construction
  line L18 (-55, 736.4) -> (-105, 736.4) construction
  line L19 (-105, 736.4) -> (-105, 507.1) construction
  circle A0 centre (-56.4849, 14.6151) radius 2.1
  circle A1 centre (-56.4849, 246.8849) radius 2.1
  circle A2 centre (-56.4849, 260.1151) radius 2.1
  circle A3 centre (-56.4849, 492.3849) radius 2.1
  circle A4 centre (-56.4849, 505.6151) radius 2.1
  circle A5 centre (-56.4849, 737.8849) radius 2.1
  circle A6 centre (-56.4849, 751.1151) radius 2.1
extrude "Догбон Ø4,2 мм Тело 03" cut sketch "Sketch5" along normal mid plane 80 bodies 36 in component "ДСП 16 — ламель прямая 982х100х16 мм — 8 шт"
sketch "Sketch6" plane through (592, 0, 0) normal (-1, 0, 0) x (0, 0, 1) in component "ДСП 16 — ламель прямая 982х100х16 мм — 8 шт"
  line L0 (30, 982) -> (5, 982) construction
  line L1 (5, 982) -> (5, 0) construction
  line L2 (5, 0) -> (55, 0) construction
  line L3 (55, 0) -> (55, 16) construction
  line L4 (55, 16) -> (105, 16) construction
  line L5 (105, 16) -> (105, 245.5) construction
  line L6 (105, 245.5) -> (55, 245.5) construction
  line L7 (55, 245.5) -> (55, 261.5) construction
  line L8 (55, 261.5) -> (105, 261.5) construction
  line L9 (105, 261.5) -> (105, 491) construction
  line L10 (105, 491) -> (55, 491) construction
  line L11 (55, 491) -> (55, 507) construction
  line L12 (55, 507) -> (105, 507) construction
  line L13 (105, 507) -> (105, 736.5) construction
  line L14 (105, 736.5) -> (55, 736.5) construction
  line L15 (55, 736.5) -> (55, 752.5) construction
  line L16 (55, 752.5) -> (105, 752.5) construction
  line L17 (105, 752.5) -> (105, 850) construction
  line L18 (105, 850) -> (30, 850) construction
  line L19 (30, 850) -> (30, 982) construction
  line L20 (55, -0.1) -> (107, -0.1)
  line L21 (107, -0.1) -> (107, 16.1)
  line L22 (107, 16.1) -> (55, 16.1)
  line L23 (55, 16.1) -> (55, -0.1)
  line L24 (55, 245.4) -> (107, 245.4)
  line L25 (107, 245.4) -> (107, 261.6)
  line L26 (107, 261.6) -> (55, 261.6)
  line L27 (55, 261.6) -> (55, 245.4)
  line L28 (55, 490.9) -> (107, 490.9)
  line L29 (107, 490.9) -> (107, 507.1)
  line L30 (107, 507.1) -> (55, 507.1)
  line L31 (55, 507.1) -> (55, 490.9)
  line L32 (55, 736.4) -> (107, 736.4)
  line L33 (107, 736.4) -> (107, 752.6)
  line L34 (107, 752.6) -> (55, 752.6)
  line L35 (55, 752.6) -> (55, 736.4)
extrude "Зазор паза +0,2 мм Тело 05" cut sketch "Sketch6" along normal mid plane 80 bodies 38 in component "ДСП 16 — ламель прямая 982х100х16 мм — 8 шт"
sketch "Sketch7" plane through (608, 0, 0) normal (1, 0, 0) x (0, 0, -1) in component "ДСП 16 — ламель прямая 982х100х16 мм — 8 шт"
  line L0 (-105, 507.1) -> (-55, 507.1) construction
  line L1 (-55, 507.1) -> (-55, 490.9) construction
  line L2 (-55, 490.9) -> (-105, 490.9) construction
  line L3 (-105, 490.9) -> (-105, 261.6) construction
  line L4 (-105, 261.6) -> (-55, 261.6) construction
  line L5 (-55, 261.6) -> (-55, 245.4) construction
  line L6 (-55, 245.4) -> (-105, 245.4) construction
  line L7 (-105, 245.4) -> (-105, 16.1) construction
  line L8 (-105, 16.1) -> (-55, 16.1) construction
  line L9 (-55, 16.1) -> (-55, 0) construction
  line L10 (-55, 0) -> (-5, 0) construction
  line L11 (-5, 0) -> (-5, 982) construction
  line L12 (-5, 982) -> (-30, 982) construction
  line L13 (-30, 982) -> (-30, 850) construction
  line L14 (-30, 850) -> (-105, 850) construction
  line L15 (-105, 850) -> (-105, 752.6) construction
  line L16 (-105, 752.6) -> (-55, 752.6) construction
  line L17 (-55, 752.6) -> (-55, 736.4) construction
  line L18 (-55, 736.4) -> (-105, 736.4) construction
  line L19 (-105, 736.4) -> (-105, 507.1) construction
  circle A0 centre (-56.4849, 14.6151) radius 2.1
  circle A1 centre (-56.4849, 246.8849) radius 2.1
  circle A2 centre (-56.4849, 260.1151) radius 2.1
  circle A3 centre (-56.4849, 492.3849) radius 2.1
  circle A4 centre (-56.4849, 505.6151) radius 2.1
  circle A5 centre (-56.4849, 737.8849) radius 2.1
  circle A6 centre (-56.4849, 751.1151) radius 2.1
extrude "Догбон Ø4,2 мм Тело 05" cut sketch "Sketch7" along normal mid plane 80 bodies 38 in component "ДСП 16 — ламель прямая 982х100х16 мм — 8 шт"
sketch "Sketch8" plane through (792, 0, 0) normal (-1, 0, 0) x (0, 0, 1) in component "ДСП 16 — ламель прямая 982х100х16 мм — 8 шт"
  line L0 (30, 982) -> (5, 982) construction
  line L1 (5, 982) -> (5, 0) construction
  line L2 (5, 0) -> (55, 0) construction
  line L3 (55, 0) -> (55, 16) construction
  line L4 (55, 16) -> (105, 16) construction
  line L5 (105, 16) -> (105, 245.5) construction
  line L6 (105, 245.5) -> (55, 245.5) construction
  line L7 (55, 245.5) -> (55, 261.5) construction
  line L8 (55, 261.5) -> (105, 261.5) construction
  line L9 (105, 261.5) -> (105, 491) construction
  line L10 (105, 491) -> (55, 491) construction
  line L11 (55, 491) -> (55, 507) construction
  line L12 (55, 507) -> (105, 507) construction
  line L13 (105, 507) -> (105, 736.5) construction
  line L14 (105, 736.5) -> (55, 736.5) construction
  line L15 (55, 736.5) -> (55, 752.5) construction
  line L16 (55, 752.5) -> (105, 752.5) construction
  line L17 (105, 752.5) -> (105, 850) construction
  line L18 (105, 850) -> (30, 850) construction
  line L19 (30, 850) -> (30, 982) construction
  line L20 (55, -0.1) -> (107, -0.1)
  line L21 (107, -0.1) -> (107, 16.1)
  line L22 (107, 16.1) -> (55, 16.1)
  line L23 (55, 16.1) -> (55, -0.1)
  line L24 (55, 245.4) -> (107, 245.4)
  line L25 (107, 245.4) -> (107, 261.6)
  line L26 (107, 261.6) -> (55, 261.6)
  line L27 (55, 261.6) -> (55, 245.4)
  line L28 (55, 490.9) -> (107, 490.9)
  line L29 (107, 490.9) -> (107, 507.1)
  line L30 (107, 507.1) -> (55, 507.1)
  line L31 (55, 507.1) -> (55, 490.9)
  line L32 (55, 736.4) -> (107, 736.4)
  line L33 (107, 736.4) -> (107, 752.6)
  line L34 (107, 752.6) -> (55, 752.6)
  line L35 (55, 752.6) -> (55, 736.4)
extrude "Зазор паза +0,2 мм Тело 07" cut sketch "Sketch8" along normal mid plane 80 bodies 40 in component "ДСП 16 — ламель прямая 982х100х16 мм — 8 шт"
sketch "Sketch9" plane through (808, 0, 0) normal (1, 0, 0) x (0, 0, -1) in component "ДСП 16 — ламель прямая 982х100х16 мм — 8 шт"
  line L0 (-105, 507.1) -> (-55, 507.1) construction
  line L1 (-55, 507.1) -> (-55, 490.9) construction
  line L2 (-55, 490.9) -> (-105, 490.9) construction
  line L3 (-105, 490.9) -> (-105, 261.6) construction
  line L4 (-105, 261.6) -> (-55, 261.6) construction
  line L5 (-55, 261.6) -> (-55, 245.4) construction
  line L6 (-55, 245.4) -> (-105, 245.4) construction
  line L7 (-105, 245.4) -> (-105, 16.1) construction
  line L8 (-105, 16.1) -> (-55, 16.1) construction
  line L9 (-55, 16.1) -> (-55, 0) construction
  line L10 (-55, 0) -> (-5, 0) construction
  line L11 (-5, 0) -> (-5, 982) construction
  line L12 (-5, 982) -> (-30, 982) construction
  line L13 (-30, 982) -> (-30, 850) construction
  line L14 (-30, 850) -> (-105, 850) construction
  line L15 (-105, 850) -> (-105, 752.6) construction
  line L16 (-105, 752.6) -> (-55, 752.6) construction
  line L17 (-55, 752.6) -> (-55, 736.4) construction
  line L18 (-55, 736.4) -> (-105, 736.4) construction
  line L19 (-105, 736.4) -> (-105, 507.1) construction
  circle A0 centre (-56.4849, 14.6151) radius 2.1
  circle A1 centre (-56.4849, 246.8849) radius 2.1
  circle A2 centre (-56.4849, 260.1151) radius 2.1
  circle A3 centre (-56.4849, 492.3849) radius 2.1
  circle A4 centre (-56.4849, 505.6151) radius 2.1
  circle A5 centre (-56.4849, 737.8849) radius 2.1
  circle A6 centre (-56.4849, 751.1151) radius 2.1
extrude "Догбон Ø4,2 мм Тело 07" cut sketch "Sketch9" along normal mid plane 80 bodies 40 in component "ДСП 16 — ламель прямая 982х100х16 мм — 8 шт"
sketch "Sketch10" plane through (208, 0, 0) normal (1, 0, 0) x (0, 0, -1) in component "ДСП 16 — ламель прямая 982х100х16 мм — 8 шт"
  line L0 (-270, 982) -> (-295, 982) construction
  line L1 (-295, 982) -> (-295, 0) construction
  line L2 (-295, 0) -> (-245, 0) construction
  line L3 (-245, 0) -> (-245, 16) construction
  line L4 (-245, 16) -> (-195, 16) construction
  line L5 (-195, 16) -> (-195, 245.5) construction
  line L6 (-195, 245.5) -> (-245, 245.5) construction
  line L7 (-245, 245.5) -> (-245, 261.5) construction
  line L8 (-245, 261.5) -> (-195, 261.5) construction
  line L9 (-195, 261.5) -> (-195, 491) construction
  line L10 (-195, 491) -> (-245, 491) construction
  line L11 (-245, 491) -> (-245, 507) construction
  line L12 (-245, 507) -> (-195, 507) construction
  line L13 (-195, 507) -> (-195, 736.5) construction
  line L14 (-195, 736.5) -> (-245, 736.5) construction
  line L15 (-245, 736.5) -> (-245, 752.5) construction
  line L16 (-245, 752.5) -> (-195, 752.5) construction
  line L17 (-195, 752.5) -> (-195, 850) construction
  line L18 (-195, 850) -> (-270, 850) construction
  line L19 (-270, 850) -> (-270, 982) construction
  line L20 (-245, -0.1) -> (-193, -0.1)
  line L21 (-193, -0.1) -> (-193, 16.1)
  line L22 (-193, 16.1) -> (-245, 16.1)
  line L23 (-245, 16.1) -> (-245, -0.1)
  line L24 (-245, 245.4) -> (-193, 245.4)
  line L25 (-193, 245.4) -> (-193, 261.6)
  line L26 (-193, 261.6) -> (-245, 261.6)
  line L27 (-245, 261.6) -> (-245, 245.4)
  line L28 (-245, 490.9) -> (-193, 490.9)
  line L29 (-193, 490.9) -> (-193, 507.1)
  line L30 (-193, 507.1) -> (-245, 507.1)
  line L31 (-245, 507.1) -> (-245, 490.9)
  line L32 (-245, 736.4) -> (-193, 736.4)
  line L33 (-193, 736.4) -> (-193, 752.6)
  line L34 (-193, 752.6) -> (-245, 752.6)
  line L35 (-245, 752.6) -> (-245, 736.4)
extrude "Зазор паза +0,2 мм Тело 08" cut sketch "Sketch10" along normal mid plane 80 bodies 41 in component "ДСП 16 — ламель прямая 982х100х16 мм — 8 шт"
sketch "Sketch11" plane through (192, 0, 0) normal (-1, 0, 0) x (0, 0, 1) in component "ДСП 16 — ламель прямая 982х100х16 мм — 8 шт"
  line L0 (195, 507.1) -> (245, 507.1) construction
  line L1 (245, 507.1) -> (245, 490.9) construction
  line L2 (245, 490.9) -> (195, 490.9) construction
  line L3 (195, 490.9) -> (195, 261.6) construction
  line L4 (195, 261.6) -> (245, 261.6) construction
  line L5 (245, 261.6) -> (245, 245.4) construction
  line L6 (245, 245.4) -> (195, 245.4) construction
  line L7 (195, 245.4) -> (195, 16.1) construction
  line L8 (195, 16.1) -> (245, 16.1) construction
  line L9 (245, 16.1) -> (245, 0) construction
  line L10 (245, 0) -> (295, 0) construction
  line L11 (295, 0) -> (295, 982) construction
  line L12 (295, 982) -> (270, 982) construction
  line L13 (270, 982) -> (270, 850) construction
  line L14 (270, 850) -> (195, 850) construction
  line L15 (195, 850) -> (195, 752.6) construction
  line L16 (195, 752.6) -> (245, 752.6) construction
  line L17 (245, 752.6) -> (245, 736.4) construction
  line L18 (245, 736.4) -> (195, 736.4) construction
  line L19 (195, 736.4) -> (195, 507.1) construction
  circle A0 centre (243.5151, 14.6151) radius 2.1
  circle A1 centre (243.5151, 246.8849) radius 2.1
  circle A2 centre (243.5151, 260.1151) radius 2.1
  circle A3 centre (243.5151, 492.3849) radius 2.1
  circle A4 centre (243.5151, 505.6151) radius 2.1
  circle A5 centre (243.5151, 737.8849) radius 2.1
  circle A6 centre (243.5151, 751.1151) radius 2.1
extrude "Догбон Ø4,2 мм Тело 08" cut sketch "Sketch11" along normal mid plane 80 bodies 41 in component "ДСП 16 — ламель прямая 982х100х16 мм — 8 шт"
sketch "Sketch12" plane through (408, 0, 0) normal (1, 0, 0) x (0, 0, -1) in component "ДСП 16 — ламель прямая 982х100х16 мм — 8 шт"
  line L0 (-270, 982) -> (-295, 982) construction
  line L1 (-295, 982) -> (-295, 0) construction
  line L2 (-295, 0) -> (-245, 0) construction
  line L3 (-245, 0) -> (-245, 16) construction
  line L4 (-245, 16) -> (-195, 16) construction
  line L5 (-195, 16) -> (-195, 245.5) construction
  line L6 (-195, 245.5) -> (-245, 245.5) construction
  line L7 (-245, 245.5) -> (-245, 261.5) construction
  line L8 (-245, 261.5) -> (-195, 261.5) construction
  line L9 (-195, 261.5) -> (-195, 491) construction
  line L10 (-195, 491) -> (-245, 491) construction
  line L11 (-245, 491) -> (-245, 507) construction
  line L12 (-245, 507) -> (-195, 507) construction
  line L13 (-195, 507) -> (-195, 736.5) construction
  line L14 (-195, 736.5) -> (-245, 736.5) construction
  line L15 (-245, 736.5) -> (-245, 752.5) construction
  line L16 (-245, 752.5) -> (-195, 752.5) construction
  line L17 (-195, 752.5) -> (-195, 850) construction
  line L18 (-195, 850) -> (-270, 850) construction
  line L19 (-270, 850) -> (-270, 982) construction
  line L20 (-245, -0.1) -> (-193, -0.1)
  line L21 (-193, -0.1) -> (-193, 16.1)
  line L22 (-193, 16.1) -> (-245, 16.1)
  line L23 (-245, 16.1) -> (-245, -0.1)
  line L24 (-245, 245.4) -> (-193, 245.4)
  line L25 (-193, 245.4) -> (-193, 261.6)
  line L26 (-193, 261.6) -> (-245, 261.6)
  line L27 (-245, 261.6) -> (-245, 245.4)
  line L28 (-245, 490.9) -> (-193, 490.9)
  line L29 (-193, 490.9) -> (-193, 507.1)
  line L30 (-193, 507.1) -> (-245, 507.1)
  line L31 (-245, 507.1) -> (-245, 490.9)
  line L32 (-245, 736.4) -> (-193, 736.4)
  line L33 (-193, 736.4) -> (-193, 752.6)
  line L34 (-193, 752.6) -> (-245, 752.6)
  line L35 (-245, 752.6) -> (-245, 736.4)
extrude "Зазор паза +0,2 мм Тело 10" cut sketch "Sketch12" along normal mid plane 80 bodies 43 in component "ДСП 16 — ламель прямая 982х100х16 мм — 8 шт"
sketch "Sketch13" plane through (392, 0, 0) normal (-1, 0, 0) x (0, 0, 1) in component "ДСП 16 — ламель прямая 982х100х16 мм — 8 шт"
  line L0 (195, 507.1) -> (245, 507.1) construction
  line L1 (245, 507.1) -> (245, 490.9) construction
  line L2 (245, 490.9) -> (195, 490.9) construction
  line L3 (195, 490.9) -> (195, 261.6) construction
  line L4 (195, 261.6) -> (245, 261.6) construction
  line L5 (245, 261.6) -> (245, 245.4) construction
  line L6 (245, 245.4) -> (195, 245.4) construction
  line L7 (195, 245.4) -> (195, 16.1) construction
  line L8 (195, 16.1) -> (245, 16.1) construction
  line L9 (245, 16.1) -> (245, 0) construction
  line L10 (245, 0) -> (295, 0) construction
  line L11 (295, 0) -> (295, 982) construction
  line L12 (295, 982) -> (270, 982) construction
  line L13 (270, 982) -> (270, 850) construction
  line L14 (270, 850) -> (195, 850) construction
  line L15 (195, 850) -> (195, 752.6) construction
  line L16 (195, 752.6) -> (245, 752.6) construction
  line L17 (245, 752.6) -> (245, 736.4) construction
  line L18 (245, 736.4) -> (195, 736.4) construction
  line L19 (195, 736.4) -> (195, 507.1) construction
  circle A0 centre (243.5151, 14.6151) radius 2.1
  circle A1 centre (243.5151, 246.8849) radius 2.1
  circle A2 centre (243.5151, 260.1151) radius 2.1
  circle A3 centre (243.5151, 492.3849) radius 2.1
  circle A4 centre (243.5151, 505.6151) radius 2.1
  circle A5 centre (243.5151, 737.8849) radius 2.1
  circle A6 centre (243.5151, 751.1151) radius 2.1
extrude "Догбон Ø4,2 мм Тело 10" cut sketch "Sketch13" along normal mid plane 80 bodies 43 in component "ДСП 16 — ламель прямая 982х100х16 мм — 8 шт"